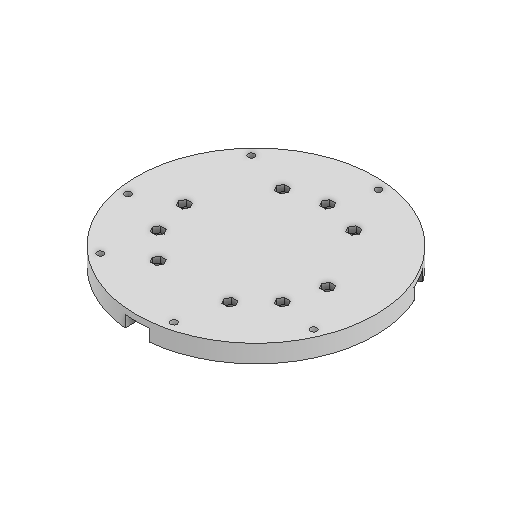
# Autodesk Inventor part: 3DP_PLA_A_Axis_Bearing_Base_Stand_Mount_REVB
Saved by Autodesk Inventor 2027 (Build 310192060, 192F)
## iProperties
Created: 2026-01-18
Part Number: 3DP_PLA_A_Axis_Bearing_Base_Stand_Mount_REVB
Material: Generic
Document SubType Name: Modeling
Designer: Andrzej
Density: 1 g/cm^3
Appearance: Default
Author: Andrzej
Autodesk Inventor part; units mm, degrees
ref_plane "YZ Plane" through (0, 0, 0) normal (1, 0, 0) x (0, 1, 0)
ref_plane "XZ Plane" through (0, 0, 0) normal (0, 1, 0) x (-1, 0, 0)
ref_plane "XY Plane" through (0, 0, 0) normal (0, 0, 1) x (1, 0, 0)
sketch "Sketch5" plane through (0, 0, 0) normal (0, 1, 0) x (-1, 0, 0)
  circle A0 centre (0, 0) radius 100.1
  line L0 (-10.1, 99.5892) -> (-10.1, 0)
  line L1 (10.1, 99.5892) -> (10.1, 0)
  line L2 (-91.2967, -41.0477) -> (-5.05, 8.7469)
  line L3 (-81.1967, -58.5414) -> (5.05, -8.7469)
  line L4 (81.1967, -58.5414) -> (-5.05, -8.7469)
  line L5 (91.2967, -41.0477) -> (5.05, 8.7469)
  line L6 (10.1, 5.8312) -> (0, -11.6625)
  line L7 (0, -11.6625) -> (-10.1, 5.8312)
  line L8 (-10.1, 5.8312) -> (10.1, 5.8312)
  line L9 (0, 0) -> (0, -118) construction
  line L10 (59.4579, 70.8591) -> (0, 0)
  line L11 (91.0947, 16.0625) -> (0, 0)
  point P0 (-80.1073, -46.25)
  point P1 (-10.7386, -91.8745)
  point P2 (67.2821, -63.4774)
  point P3 (-84.935, 36.6374)
  point P4 (-21.332, 90.0067)
  point P5 (-10.25, 5.9178)
  point P6 (81.1967, -58.5414)
  point P7 (0, -11.8357)
  point P8 (-81.1967, -58.5414)
  point P9 (10.25, 5.9178)
  point P10 (91.2967, -41.0477)
  dimension "d62" = 200.2
  dimension "d63" = 20.2
  dimension "d64" = 10.1
  dimension "d67" = 360
  dimension "d69" = 92.5
  dimension "d72" = 160
  dimension "d76" = 160
  dimension "d123" = 40
  dimension "d124" = 120
  dimension "d125" = 40
  constraints: 24 end point, 6 point on line, 3 vertical, 2 horizontal alignment, 2 point on circle, 1 centre point, 1 coincident, 27 other
  measures "d62" diameter of A0
  measures "d63" distance between parallel lines of L1 L0
  measures "d64" distance from line of L1 point (0, 0)
  measures "d69" distance of point (0, 0) point (-80.107, -46.25)
  measures "d123" angle of L11 L10
  measures "d124" angle of L5 L1
  measures "d125" angle of L10 L1
extrude "Extrusion4" add sketch "Sketch5" along normal blind 5
extrude "Extrusion5" add sketch "Sketch5" against normal blind 10 contours A0 L5 L1 | L0 L2 A0 | A0 L3 L4
hole "Hole5" at (-67.2821, 0, -63.4774) at (-91.0947, 0, 16.0625) at (21.332, 0, 90.0067) at (10.7386, 0, -91.8745) at (84.935, 0, 36.6374) at (-59.4579, 0, 70.8591) direction (0, 1, 0) diameter 5.5 end through all both
sketch "Sketch6" plane through (0, -10, 0) normal (0, -1, 0) x (1, 0, 0)
  circle A0 centre (-91.0947, 16.0625) radius 2.75 projected
  circle A1 centre (-67.2821, -63.4774) radius 2.75 projected
  arc A2 (-10.1, 99.5892) -> (-91.2967, -41.0477) centre (0, 0) ccw projected
  circle A3 centre (21.332, 90.0067) radius 2.75 projected
  arc A4 (91.2967, -41.0477) -> (10.1, 99.5892) centre (0, 0) ccw projected
  arc A5 (-81.1967, -58.5414) -> (81.1967, -58.5414) centre (0, 0) ccw projected
  line L0 (-93.5485, 11.8125) -> (-96.0022, 16.0625)
  line L1 (-96.0022, 16.0625) -> (-93.5485, 20.3125)
  line L2 (-93.5485, 20.3125) -> (-88.641, 20.3125)
  line L3 (-88.641, 20.3125) -> (-86.1872, 16.0625)
  line L4 (-86.1872, 16.0625) -> (-88.641, 11.8125)
  line L5 (-88.641, 11.8125) -> (-93.5485, 11.8125)
  line L6 (-69.7358, -67.7274) -> (-72.1895, -63.4774)
  line L7 (-72.1895, -63.4774) -> (-69.7358, -59.2274)
  line L8 (-69.7358, -59.2274) -> (-64.8283, -59.2274)
  line L9 (-64.8283, -59.2274) -> (-62.3746, -63.4774)
  line L10 (-62.3746, -63.4774) -> (-64.8283, -67.7274)
  line L11 (-64.8283, -67.7274) -> (-69.7358, -67.7274)
  line L12 (18.8782, 85.7567) -> (16.4245, 90.0067)
  line L13 (16.4245, 90.0067) -> (18.8782, 94.2567)
  line L14 (18.8782, 94.2567) -> (23.7857, 94.2567)
  line L15 (23.7857, 94.2567) -> (26.2394, 90.0067)
  line L16 (26.2394, 90.0067) -> (23.7857, 85.7567)
  line L17 (23.7857, 85.7567) -> (18.8782, 85.7567)
  circle A6 centre (10.7386, -91.8745) radius 2.75 projected
  arc A7 (-81.1967, -58.5414) -> (81.1967, -58.5414) centre (0, 0) ccw projected
  circle A8 centre (84.935, 36.6374) radius 2.75 projected
  circle A9 centre (21.332, 90.0067) radius 2.75 projected
  arc A10 (91.2967, -41.0477) -> (10.1, 99.5892) centre (0, 0) ccw projected
  line L18 (13.1923, -87.6245) -> (15.6461, -91.8745)
  line L19 (15.6461, -91.8745) -> (13.1923, -96.1245)
  line L20 (13.1923, -96.1245) -> (8.2849, -96.1245)
  line L21 (8.2849, -96.1245) -> (5.8311, -91.8745)
  line L22 (5.8311, -91.8745) -> (8.2849, -87.6245)
  line L23 (8.2849, -87.6245) -> (13.1923, -87.6245)
  line L24 (87.3887, 40.8874) -> (89.8425, 36.6374)
  line L25 (89.8425, 36.6374) -> (87.3887, 32.3874)
  line L26 (87.3887, 32.3874) -> (82.4813, 32.3874)
  line L27 (82.4813, 32.3874) -> (80.0275, 36.6374)
  line L28 (80.0275, 36.6374) -> (82.4813, 40.8874)
  line L29 (82.4813, 40.8874) -> (87.3887, 40.8874)
  line L30 (10.1, 99.5892) -> (10.1, 5.8312) projected
  line L31 (10.1, 5.8312) -> (91.2967, -41.0477) projected
  line L32 (81.1967, -58.5414) -> (0, -11.6625) projected
  line L33 (0, -11.6625) -> (-81.1967, -58.5414) projected
  line L34 (81.1967, -58.5414) -> (0, -11.6625) projected
  line L35 (0, -11.6625) -> (-81.1967, -58.5414) projected
  line L36 (10.1, 99.5892) -> (10.1, 5.8312) projected
  line L37 (10.1, 5.8312) -> (91.2967, -41.0477) projected
  line L38 (-91.2967, -41.0477) -> (-10.1, 5.8312) projected
  line L39 (-10.1, 5.8312) -> (-10.1, 99.5892) projected
  circle A11 centre (-59.4579, 70.8591) radius 2.75 projected
  line L40 (-54.5504, 70.8591) -> (-57.0041, 66.6091)
  line L41 (-57.0041, 66.6091) -> (-61.9116, 66.6091)
  line L42 (-61.9116, 66.6091) -> (-64.3653, 70.8591)
  line L43 (-64.3653, 70.8591) -> (-61.9116, 75.1091)
  line L44 (-61.9116, 75.1091) -> (-57.0041, 75.1091)
  line L45 (-57.0041, 75.1091) -> (-54.5504, 70.8591)
  point P0 (10.7386, -91.8745)
  point P1 (84.935, 40.8874)
  dimension "d90" = 8.5
  dimension "d92" = 8.5
  dimension "d93" = 8.5
  dimension "d97" = 8.5
  dimension "d98" = 8.5
  dimension "d126" = 8.5
  constraints: 72 end point, 6 coincident, 1 midpoint, 78 other
  measures "d90" distance between parallel lines of L14 L17
  measures "d92" distance between parallel lines of L5 L2
  measures "d93" distance between parallel lines of L11 L8
  measures "d97" distance from line of L26 point (84.935, 40.887)
  measures "d98" distance between parallel lines of L23 L20
  measures "d126" distance between parallel lines of L41 L44
extrude "Extrusion6" cut sketch "Sketch6" against normal blind 5 contours A0 | A1 | L0 L1 L2 L3 L4 L5 | L6 L7 L8 L9 L10 L11 | L12 L13 L14 L15 L16 L17 | L18 L19 L20 L21 L22 L23 | L24 L25 L26 L27 L28 L29 | L40 L41 L42 L43 L44 L45
sketch "Sketch7" plane through (0, -10, 0) normal (0, -1, 0) x (1, 0, 0)
  line L0 (-88.641, 20.3125) -> (-86.1872, 16.0625) projected
  line L1 (-86.1872, 16.0625) -> (-88.641, 11.8125) projected
  line L2 (-88.641, 11.8125) -> (-93.5485, 11.8125) projected
  line L3 (-93.5485, 11.8125) -> (-96.0022, 16.0625) projected
  line L4 (-96.0022, 16.0625) -> (-93.5485, 20.3125) projected
  line L5 (-93.5485, 20.3125) -> (-88.641, 20.3125) projected
  line L6 (-64.8283, -59.2274) -> (-62.3746, -63.4774) projected
  line L7 (-62.3746, -63.4774) -> (-64.8283, -67.7274) projected
  line L8 (-64.8283, -67.7274) -> (-69.7358, -67.7274) projected
  line L9 (-69.7358, -67.7274) -> (-72.1895, -63.4774) projected
  line L10 (-72.1895, -63.4774) -> (-69.7358, -59.2274) projected
  line L11 (-69.7358, -59.2274) -> (-64.8283, -59.2274) projected
  arc A0 (-10.1, 99.5892) -> (-91.2967, -41.0477) centre (0, 0) ccw projected
  line L12 (82.4813, 32.3874) -> (80.0275, 36.6374) projected
  line L13 (80.0275, 36.6374) -> (82.4813, 40.8874) projected
  line L14 (82.4813, 40.8874) -> (87.3887, 40.8874) projected
  line L15 (87.3887, 40.8874) -> (89.8425, 36.6374) projected
  line L16 (89.8425, 36.6374) -> (87.3887, 32.3874) projected
  line L17 (87.3887, 32.3874) -> (82.4813, 32.3874) projected
  line L18 (23.7857, 94.2567) -> (26.2394, 90.0067) projected
  line L19 (26.2394, 90.0067) -> (23.7857, 85.7567) projected
  line L20 (23.7857, 85.7567) -> (18.8782, 85.7567) projected
  line L21 (18.8782, 85.7567) -> (16.4245, 90.0067) projected
  line L22 (16.4245, 90.0067) -> (18.8782, 94.2567) projected
  line L23 (18.8782, 94.2567) -> (23.7857, 94.2567) projected
  arc A1 (91.2967, -41.0477) -> (10.1, 99.5892) centre (0, 0) ccw projected
  line L24 (8.2849, -96.1245) -> (5.8311, -91.8745) projected
  line L25 (5.8311, -91.8745) -> (8.2849, -87.6245) projected
  line L26 (8.2849, -87.6245) -> (13.1923, -87.6245) projected
  line L27 (13.1923, -87.6245) -> (15.6461, -91.8745) projected
  line L28 (15.6461, -91.8745) -> (13.1923, -96.1245) projected
  line L29 (13.1923, -96.1245) -> (8.2849, -96.1245) projected
  arc A2 (-81.1967, -58.5414) -> (81.1967, -58.5414) centre (0, 0) ccw projected
  line L30 (81.1967, -58.5414) -> (0, -11.6625) projected
  line L31 (0, -11.6625) -> (-81.1967, -58.5414) projected
  line L32 (10.1, 99.5892) -> (10.1, 5.8312) projected
  line L33 (10.1, 5.8312) -> (91.2967, -41.0477) projected
  line L34 (-91.2967, -41.0477) -> (-10.1, 5.8312) projected
  line L35 (-10.1, 5.8312) -> (-10.1, 99.5892) projected
  point P0 (0, -60)
  point P1 (30, -51.9615)
  point P2 (51.9615, -30)
  point P3 (60, 0)
  point P4 (51.9615, 30)
  point P5 (30, 51.9615)
  point P6 (0, 60)
  point P7 (-30, 51.9615)
  point P8 (-51.9615, 30)
  point P9 (-60, 0)
  point P10 (-51.9615, -30)
  point P11 (-30, -51.9615)
  dimension "d99" = 60
  dimension "d102" = 360
  constraints: 1 vertical alignment, 13 other
  measures "d99" distance of point (0, 0) point (0, -60)
hole "Hole6" at (0, -10, -60) at (30, -10, -51.9615) at (60, -10, 0) at (51.9615, -10, 30) at (30, -10, 51.9615) at (-30, -10, 51.9615) at (-51.9615, -10, 30) at (-60, -10, 0) at (-30, -10, -51.9615) direction (0, 1, 0) diameter 5.5 end through all
sketch "Sketch9" plane through (0, 5, 0) normal (0, 1, 0) x (1, 0, 0)
  circle A0 centre (-30, 51.9615) radius 2.75 projected
  circle A1 centre (-60, 0) radius 2.75 projected
  circle A2 centre (-51.9615, -30) radius 2.75 projected
  circle A3 centre (-30, -51.9615) radius 2.75 projected
  circle A4 centre (30, -51.9615) radius 2.75 projected
  circle A5 centre (51.9615, -30) radius 2.75 projected
  circle A6 centre (60, 0) radius 2.75 projected
  circle A7 centre (30, 51.9615) radius 2.75 projected
  circle A8 centre (0, 60) radius 2.75 projected
  circle A9 centre (84.935, -36.6374) radius 2.75 projected
  circle A10 centre (10.7386, 91.8745) radius 2.75 projected
  circle A11 centre (21.332, -90.0067) radius 2.75 projected
  circle A12 centre (-91.0947, -16.0625) radius 2.75 projected
  circle A13 centre (-67.2821, 63.4774) radius 2.75 projected
  circle A14 centre (0, 0) radius 100.1 projected
  line L0 (2.4537, 64.25) -> (4.9075, 60)
  line L1 (4.9075, 60) -> (2.4537, 55.75)
  line L2 (2.4537, 55.75) -> (-2.4537, 55.75)
  line L3 (-2.4537, 55.75) -> (-4.9075, 60)
  line L4 (-4.9075, 60) -> (-2.4537, 64.25)
  line L5 (-2.4537, 64.25) -> (2.4537, 64.25)
  line L6 (-27.5463, 56.2115) -> (-25.0925, 51.9615)
  line L7 (-25.0925, 51.9615) -> (-27.5463, 47.7115)
  line L8 (-27.5463, 47.7115) -> (-32.4537, 47.7115)
  line L9 (-32.4537, 47.7115) -> (-34.9075, 51.9615)
  line L10 (-34.9075, 51.9615) -> (-32.4537, 56.2115)
  line L11 (-32.4537, 56.2115) -> (-27.5463, 56.2115)
  line L12 (32.4537, 56.2115) -> (34.9075, 51.9615)
  line L13 (34.9075, 51.9615) -> (32.4537, 47.7115)
  line L14 (32.4537, 47.7115) -> (27.5463, 47.7115)
  line L15 (27.5463, 47.7115) -> (25.0925, 51.9615)
  line L16 (25.0925, 51.9615) -> (27.5463, 56.2115)
  line L17 (27.5463, 56.2115) -> (32.4537, 56.2115)
  line L18 (-57.5463, 4.25) -> (-55.0925, 0)
  line L19 (-55.0925, 0) -> (-57.5463, -4.25)
  line L20 (-57.5463, -4.25) -> (-62.4537, -4.25)
  line L21 (-62.4537, -4.25) -> (-64.9075, 0)
  line L22 (-64.9075, 0) -> (-62.4537, 4.25)
  line L23 (-62.4537, 4.25) -> (-57.5463, 4.25)
  line L24 (-49.5406, -25.7312) -> (-47.0542, -29.9622)
  line L25 (-47.0542, -29.9622) -> (-49.4752, -34.231)
  line L26 (-49.4752, -34.231) -> (-54.3825, -34.2688)
  line L27 (-54.3825, -34.2688) -> (-56.8689, -30.0378)
  line L28 (-56.8689, -30.0378) -> (-54.4479, -25.769)
  line L29 (-54.4479, -25.769) -> (-49.5406, -25.7312)
  line L30 (-27.5462, -47.7115) -> (-25.0925, -51.9616)
  line L31 (-25.0925, -51.9616) -> (-27.5463, -56.2115)
  line L32 (-27.5463, -56.2115) -> (-32.4538, -56.2115)
  line L33 (-32.4538, -56.2115) -> (-34.9075, -51.9615)
  line L34 (-34.9075, -51.9615) -> (-32.4537, -47.7115)
  line L35 (-32.4537, -47.7115) -> (-27.5462, -47.7115)
  line L36 (32.4012, -47.6816) -> (34.9071, -51.9011)
  line L37 (34.9071, -51.9011) -> (32.5059, -56.181)
  line L38 (32.5059, -56.181) -> (27.5988, -56.2414)
  line L39 (27.5988, -56.2414) -> (25.0929, -52.022)
  line L40 (25.0929, -52.022) -> (27.4941, -47.7421)
  line L41 (27.4941, -47.7421) -> (32.4012, -47.6816)
  line L42 (54.4153, -25.75) -> (56.869, -30)
  line L43 (56.869, -30) -> (54.4153, -34.25)
  line L44 (54.4153, -34.25) -> (49.5078, -34.25)
  line L45 (49.5078, -34.25) -> (47.054, -30)
  line L46 (47.054, -30) -> (49.5078, -25.75)
  line L47 (49.5078, -25.75) -> (54.4153, -25.75)
  line L48 (62.4537, 4.25) -> (64.9075, 0)
  line L49 (64.9075, 0) -> (62.4537, -4.25)
  line L50 (62.4537, -4.25) -> (57.5463, -4.25)
  line L51 (57.5463, -4.25) -> (55.0925, 0)
  line L52 (55.0925, 0) -> (57.5463, 4.25)
  line L53 (57.5463, 4.25) -> (62.4537, 4.25)
  point P0 (29.9476, -47.7118)
  dimension "d111" = 8.5
  dimension "d112" = 8.5
  dimension "d113" = 8.5
  dimension "d114" = 8.5
  dimension "d115" = 8.5
  dimension "d116" = 8.5
  dimension "d117" = 8.5
  dimension "d118" = 8.5
  dimension "d119" = 8.5
  constraints: 108 end point, 9 coincident, 1 midpoint, 1 point on line, 117 other
  measures "d111" distance between parallel lines of L53 L50
  measures "d112" distance between parallel lines of L44 L47
  measures "d113" distance between parallel lines of L38 L41
  measures "d114" distance between parallel lines of L35 L32
  measures "d115" distance between parallel lines of L29 L26
  measures "d116" distance between parallel lines of L23 L20
  measures "d117" distance between parallel lines of L11 L8
  measures "d118" distance between parallel lines of L5 L2
  measures "d119" distance between parallel lines of L17 L14
extrude "Extrusion7" cut sketch "Sketch9" against normal blind 5 contours A4 | L0 L1 L2 L3 L4 L5 | L6 L7 L8 L9 L10 L11 | L12 L13 L14 L15 L16 L17 | L18 L19 L20 L21 L22 L23 | L24 L25 L26 L27 L28 L29 | L30 L31 L32 L33 L34 L35 | L36 L37 L38 L39 L40 L41 | L42 L43 L44 L45 L46 L47 | L48 L49 L50 L51 L52 L53
equation "\"d64\" = 0.5 * d63"
equation "\"d114\" = d113"
equation "\"d115\" = d114"
equation "\"d116\" = d115"
equation "\"d117\" = d116"
equation "\"d118\" = d117"
equation "\"d119\" = d117"
body "Solid2"
